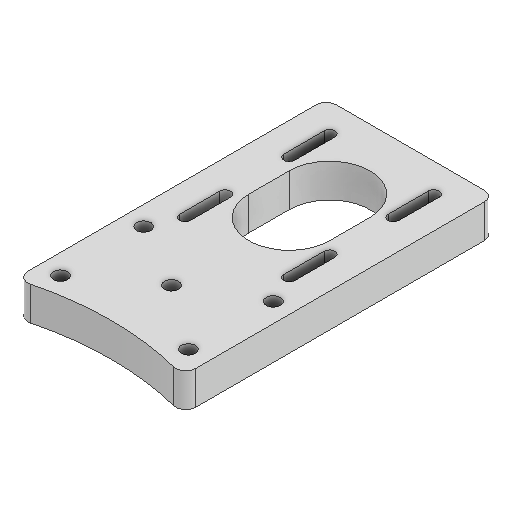
# Autodesk Inventor part: 3DP_PLA_A_Axis_Stepper_Mount_REVB
Saved by Autodesk Inventor 2027 (Build 310192060, 192F)
## iProperties
Created: 2026-01-06
Part Number: 3DP_PLA_A_Axis_Stepper_Mount_REVB
Material: Generic
Document SubType Name: Modeling
Designer: User
Density: 1 g/cm^3
Appearance: Default
Author: User
Autodesk Inventor part; units mm, degrees
ref_plane "YZ Plane" through (0, 0, 0) normal (1, 0, 0) x (0, 1, 0)
ref_plane "XZ Plane" through (0, 0, 0) normal (0, 1, 0) x (-1, 0, 0)
ref_plane "XY Plane" through (0, 0, 0) normal (0, 0, 1) x (1, 0, 0)
sketch "Sketch1" plane through (0, 0, 0) normal (0, 1, 0) x (-1, 0, 0)
  circle A0 centre (0, 0) radius 75
  circle A1 centre (0, 0) radius 85
  circle A2 centre (0, 0) radius 67.5
  circle A3 centre (0, 0) radius 100
  line L0 (25, -81.2404) -> (25, -110)
  line L1 (25, -110) -> (-25, -110)
  line L2 (-25, -110) -> (-25, -81.2404)
  line L3 (-25, -110) -> (-25, -175)
  line L4 (-25, -175) -> (25, -175)
  line L5 (25, -175) -> (25, -110)
  line L6 (0, -139) -> (0, -151) construction
  line L7 (-12, -139) -> (-12, -151)
  line L8 (12, -151) -> (12, -139)
  arc A4 (12, -139) -> (-12, -139) centre (0, -139) ccw
  arc A5 (-12, -151) -> (12, -151) centre (0, -151) ccw
  line L9 (15.5, -123.5) -> (15.5, -135.5) construction
  line L10 (13.9, -123.5) -> (13.9, -135.5)
  line L11 (17.1, -135.5) -> (17.1, -123.5)
  arc A6 (17.1, -123.5) -> (13.9, -123.5) centre (15.5, -123.5) ccw
  arc A7 (13.9, -135.5) -> (17.1, -135.5) centre (15.5, -135.5) ccw
  line L12 (15.5, -154.5) -> (15.5, -166.5) construction
  line L13 (13.9, -154.5) -> (13.9, -166.5)
  line L14 (17.1, -166.5) -> (17.1, -154.5)
  arc A8 (17.1, -154.5) -> (13.9, -154.5) centre (15.5, -154.5) ccw
  arc A9 (13.9, -166.5) -> (17.1, -166.5) centre (15.5, -166.5) ccw
  line L15 (-15.5, -123.5) -> (-15.5, -135.5) construction
  line L16 (-17.1, -123.5) -> (-17.1, -135.5)
  line L17 (-13.9, -135.5) -> (-13.9, -123.5)
  arc A10 (-13.9, -123.5) -> (-17.1, -123.5) centre (-15.5, -123.5) ccw
  arc A11 (-17.1, -135.5) -> (-13.9, -135.5) centre (-15.5, -135.5) ccw
  line L18 (-15.5, -154.5) -> (-15.5, -166.5) construction
  line L19 (-17.1, -154.5) -> (-17.1, -166.5)
  line L20 (-13.9, -166.5) -> (-13.9, -154.5)
  arc A12 (-13.9, -154.5) -> (-17.1, -154.5) centre (-15.5, -154.5) ccw
  arc A13 (-17.1, -166.5) -> (-13.9, -166.5) centre (-15.5, -166.5) ccw
  circle A14 centre (0, -145) radius 11.075
  circle A15 centre (19.275, -115) radius 7
  circle A16 centre (19.275, -115) radius 2.1
  circle A17 centre (-19.275, -115) radius 7
  circle A18 centre (-19.275, -115) radius 2.1
  arc A19 (-25, -82.2861) -> (25, -82.2861) centre (0, 0) ccw
  point P0 (25, -96.8246)
  point P1 (-25, -96.8246)
  point P2 (0, -100)
  point P3 (19, -90)
  point P4 (-19, -90)
  point P5 (0, -104)
  point P6 (15.5, -129.5)
  point P7 (15.5, -160.5)
  point P8 (-15.5, -129.5)
  point P9 (-15.5, -160.5)
  dimension "d0" = 150
  dimension "d1" = 10
  dimension "d2" = 135
  dimension "d3" = 15
  dimension "d32" = 25
  dimension "d33" = 25
  dimension "d34" = 110
  dimension "d53" = 65
  dimension "d54" = 6
  dimension "d55" = 6
  dimension "d56" = 20
  dimension "d57" = 6
  dimension "d58" = 6
  dimension "d59" = 24
  dimension "d60" = 35
  dimension "d61" = 6
  dimension "d62" = 3.2
  dimension "d63" = 6
  dimension "d64" = 3.2
  dimension "d65" = 25
  dimension "d66" = 15.5
  dimension "d67" = 15.5
  dimension "d68" = 15.5
  dimension "d69" = 6
  dimension "d70" = 3.2
  dimension "d71" = 6
  dimension "d72" = 3.2
  dimension "d73" = 15.5
  dimension "d74" = 15.5
  dimension "d75" = 15.5
  dimension "d76" = 22.15
  dimension "d77" = 14
  dimension "d78" = 19.275
  dimension "d79" = 4.2
  dimension "d80" = 5
  dimension "d81" = 14
  dimension "d82" = 4.2
  dimension "d83" = 5
  dimension "d84" = 19.275
  dimension "d85" = 1
  dimension "d86" = 86
  constraints: 52 end point, 24 point on circle, 20 centre point, 20 tangent, 6 parallel, 6 point on line, 5 coincident, 5 midpoint, 4 perpendicular, 4 vertical, 1 horizontal alignment
  measures "d0" diameter of A0
  measures "d1" radial gap between concentric circles of A0 A1
  measures "d2" diameter of A2
  measures "d3" radial gap between concentric circles of A1 A3
  measures "d32" distance from line of point (0, 0) L0
  measures "d33" distance from line of point (0, 0) L2
  measures "d34" distance from line of point (0, 0) L1
  measures "d53" distance between parallel lines of L4 L1
  measures "d54" distance from line of L0 point (19, -90)
  measures "d55" distance from line of L2 point (-19, -90)
  measures "d56" distance from line of L1 point (19, -90)
  measures "d57" distance from line of L1 point (0, -104)
  measures "d58" distance of point (0, -145) L6.end
  measures "d59" diameter of A5
  measures "d60" distance from line of point (0, -145) L1
  measures "d61" distance of point (15.5, -129.5) L9.end
  measures "d62" diameter of A7
  measures "d63" distance of point (15.5, -160.5) L12.end
  measures "d64" diameter of A9
  measures "d65" distance from line of L5 point (0, -145)
  measures "d66" horizontal distance of point (0, -145) point (15.5, -129.5)
  measures "d67" horizontal distance of point (0, -145) point (15.5, -160.5)
  measures "d68" horizontal distance of point (0, -145) point (15.5, -129.5)
  measures "d69" distance of point (-15.5, -129.5) L15.end
  measures "d70" diameter of A11
  measures "d71" distance of point (-15.5, -160.5) L18.end
  measures "d72" diameter of A13
  measures "d73" horizontal distance of point (0, -145) point (-15.5, -129.5)
  measures "d74" horizontal distance of point (0, -145) point (-15.5, -160.5)
  measures "d75" horizontal distance of point (0, -145) point (-15.5, -129.5)
  measures "d76" diameter of A14
  measures "d77" diameter of A15
  measures "d78" horizontal distance of A15.centre point (0, -145)
  measures "d79" diameter of A16
  measures "d80" distance from line of A15.centre L1
  measures "d81" diameter of A17
  measures "d82" diameter of A18
  measures "d83" distance from line of L1 A17.centre
  measures "d84" horizontal distance of point (0, -145) A18.centre
  measures "d85" radial gap between concentric circles of A1 A19
  measures "d86" radius of A19
extrude "Extrusion6" add sketch "Sketch1" along normal blind 10 contours A19 L0 A3 L2 | A3 L0 L1 A15 A17 L2 | L1 A17 L3 | L5 A15 L1 | A17 L1 | L1 A17 L3 | A15 L5 L1 | L1 A15 | L1 A15 L5 L4 L3 A17
fillet "Fillet3" radius 3 4 edges at (25, 5, -175) (-25, 5, -175) (25, 5, -82.2861) (-25, 5, -82.2861)
hole "Hole3" at (-19, 0, -90) at (19, 0, -90) at (0, 0, -104) direction (0, 1, 0) diameter 4.2 end through all
sketch "Sketch10" plane through (0, 0, 0) normal (0, -1, 0) x (1, 0, 0)
  line L0 (-5, -100) -> (5, -100)
  line L1 (5, -100) -> (0, -95)
  line L2 (-5, -100) -> (0, -95)
  line L3 (-5, -100) -> (6.83, -100) construction
  line L4 (22, -175) -> (-22, -175) projected
  circle A0 centre (0, -104) radius 2.1 projected
  point P0 (0, 0)
  dimension "d150" = 10
  dimension "d152" = 45
  dimension "d154" = 45
  dimension "d155" = 75
  dimension "d156" = 5
  constraints: 8 end point, 2 horizontal
  measures "d150" distance of L0.start L0.end
  measures "d152" angle of L1 L0
  measures "d154" angle of L3 L2
  measures "d155" distance between parallel lines of L4 L0
  measures "d156" horizontal distance of A0.centre L0.start
extrude "Extrusion11" cut sketch "Sketch10" against normal blind 0.5 contours L2 L1 L0
equation "\"d33\" = d32"
equation "\"d61\" = d58"
equation "\"d63\" = d58"
equation "\"d67\" = d66"
equation "\"d68\" = d66"
equation "\"d69\" = d58"
equation "\"d71\" = d58"
equation "\"d74\" = d73"
equation "\"d75\" = d68"
equation "\"d84\" = d78"
body "Solid2"
